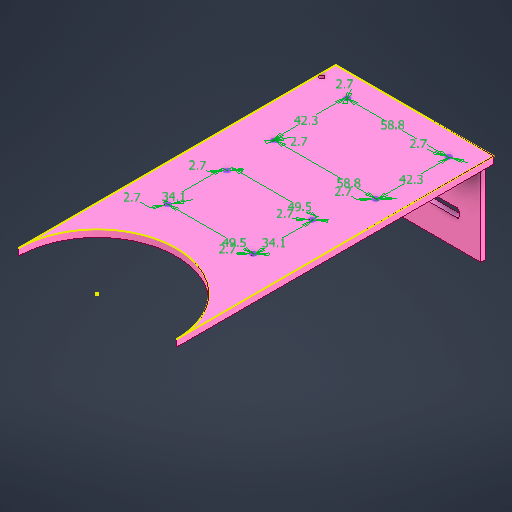
# Autodesk Inventor part: modificacao_tampa_base
Saved by Autodesk Inventor 2027.1 (Build 311270010, 270A)
## iProperties
Created: 2026-11-04
Part Number: modificacao_tampa_base
Material: Genérico
Document SubType Name: Modeling
Designer: Evellyn
Density: 1 g/cm^3
Appearance: Rosa
Author: Evellyn
Autodesk Inventor part; units mm, degrees
ref_plane "YZ Plane" through (0, 0, 0) normal (1, 0, 0) x (0, 1, 0)
ref_plane "XZ Plane" through (0, 0, 0) normal (0, 1, 0) x (-1, 0, 0)
ref_plane "XY Plane" through (0, 0, 0) normal (0, 0, 1) x (1, 0, 0)
sketch "Esboço1" plane through (0, 0, 0) normal (0, 1, 0) x (-1, 0, 0)
  line L0 (-45.75, -92) -> (45.75, -92)
  line L1 (45.75, -92) -> (45.75, 92)
  line L2 (-45.75, 92) -> (-45.75, -92)
  line L3 (-45.75, -92) -> (45.75, 92) construction
  line L4 (45.75, -92) -> (-45.75, 92) construction
  arc A0 (-45.75, 91.6728) -> (45.75, 91.6728) centre (0, 92) ccw
  arc A1 (45.75, 91.6728) -> (45.75, 92.3272) centre (0, 92) ccw
  arc A2 (-45.75, 92.3272) -> (-45.75, 91.6728) centre (0, 92) ccw
  point P0 (0, 0)
  dimension "d3" = 184
  dimension "d4" = 91.5
  constraints: 10 end point, 6 point on circle, 4 point on line, 3 centre point, 2 midpoint, 1 coincident, 1 horizontal, 1 parallel, 1 perpendicular
  measures "d3" distance of L0.end L1.end
  measures "d4" distance of L0.start L0.end
extrude "Extrusão1" add sketch "Esboço1" along normal blind 4
sketch "Esboço2" plane through (0, 0, 0) normal (0, -1, 0) x (1, 0, 0)
  line L0 (45.75, 91.6728) -> (45.75, -92) projected
  arc A0 (-45.75, 91.6728) -> (45.75, 91.6728) centre (0, 92) ccw projected
  line L1 (45.75, -92) -> (-45.75, -92) projected
  line L2 (-45.75, -92) -> (-45.75, 91.6728) projected
  line L3 (-41.75, -92) -> (41.25, -92)
  line L4 (41.25, -92) -> (41.25, -89)
  line L5 (41.25, -89) -> (-41.75, -89)
  line L6 (-41.75, -89) -> (-41.75, -92)
  line L7 (-41.75, -92) -> (41.25, -89) construction
  line L8 (41.25, -92) -> (-41.75, -89) construction
  point P0 (0, 0)
  point P1 (-0.25, -90.5)
  dimension "d7" = 3
  dimension "d8" = 4.5
  dimension "d9" = 83
  dimension "d10" = 0
  constraints: 12 end point, 2 midpoint, 2 parallel, 1 horizontal, 1 perpendicular
  measures "d7" distance of L3.end L4.end
  measures "d8" distance between parallel lines of L0 L4
  measures "d9" distance of L3.start L3.end
  measures "d10" distance between parallel lines of L1 L3
extrude "Extrusão2" add sketch "Esboço2" along normal blind 50 contours L1 L6 L5 L4
sketch "Esboço3" plane through (45.75, 4, -92) normal (0, 0, -1) x (-1, 0, 0)
  circle A0 centre (71.347, -29.4515) radius 5
  line L0 (18.0503, -33.5673) -> (36.0503, -33.5673)
  line L1 (37.0503, -34.5673) -> (37.0503, -37.5673)
  line L2 (36.0503, -38.5673) -> (18.0503, -38.5673)
  line L3 (17.0503, -37.5673) -> (17.0503, -34.5673)
  arc A1 (18.0503, -33.5673) -> (17.0503, -34.5673) centre (18.0503, -34.5673) ccw
  arc A2 (17.0503, -37.5673) -> (18.0503, -38.5673) centre (18.0503, -37.5673) ccw
  arc A3 (37.0503, -34.5673) -> (36.0503, -33.5673) centre (36.0503, -34.5673) ccw
  arc A4 (36.0503, -38.5673) -> (37.0503, -37.5673) centre (36.0503, -37.5673) ccw
  point P0 (45.75, -4)
  point P1 (37.0503, -38.5673)
  point P2 (37.0503, -33.5673)
  point P3 (17.0503, -38.5673)
  dimension "d13" = 10
  dimension "d14" = 20
  dimension "d15" = 5
  dimension "d16" = 1
  constraints: 8 end point, 8 point on circle, 8 tangent, 6 point on line, 5 centre point, 3 equal radius, 2 parallel, 1 horizontal, 1 perpendicular
  measures "d13" diameter of A0
  measures "d14" distance of point (37.05, -38.567) point (17.05, -38.567)
  measures "d15" distance of point (37.05, -33.567) point (37.05, -38.567)
  measures "d16" radius of A1
extrude "Extrusão3" cut sketch "Esboço3" against normal blind 50
sketch "Esboço4" plane through (0, 4, 0) normal (0, 1, 0) x (1, 0, 0)
  line L0 (-45.75, 92) -> (-45.75, -91.6728) projected
  arc A0 (45.75, -91.6728) -> (-45.75, -91.6728) centre (0, -92) ccw projected
  line L1 (45.75, -91.6728) -> (45.75, 92) projected
  line L2 (45.75, 92) -> (-45.75, 92) projected
  circle A1 centre (-24.3813, -26.7024) radius 1.35
  circle A2 centre (25.1187, -26.7024) radius 1.35
  circle A3 centre (-24.3813, 7.3976) radius 1.35
  circle A4 centre (25.1187, 7.3976) radius 1.35
  circle A5 centre (33.0687, 36.2863) radius 1.35
  circle A6 centre (33.0687, 78.5863) radius 1.35
  circle A7 centre (-25.7313, 36.2863) radius 1.35
  circle A8 centre (-25.7313, 78.5863) radius 1.35
  dimension "d28" = 2.7
  dimension "d31" = 2.7
  dimension "d32" = 49.5
  dimension "d33" = 2.7
  dimension "d35" = 34.1
  dimension "d36" = 2.7
  dimension "d37" = 49.5
  dimension "d38" = 34.1
  dimension "d49" = 2.7
  dimension "d52" = 2.7
  dimension "d53" = 42.3
  dimension "d62" = 2.7
  dimension "d63" = 58.8
  dimension "d64" = 2.7
  dimension "d65" = 42.3
  dimension "d66" = 58.8
  constraints: 8 centre point
  measures "d28" diameter of A1
  measures "d31" diameter of A2
  measures "d32" distance of A2.centre A1.centre
  measures "d33" diameter of A3
  measures "d35" distance of A1.centre A3.centre
  measures "d36" diameter of A4
  measures "d37" distance of A4.centre A3.centre
  measures "d38" distance of A2.centre A4.centre
  measures "d49" diameter of A5
  measures "d52" diameter of A6
  measures "d53" distance of A5.centre A6.centre
  measures "d62" diameter of A7
  measures "d63" distance of A5.centre A7.centre
  measures "d64" diameter of A8
  measures "d65" distance of A7.centre A8.centre
  measures "d66" distance of A6.centre A8.centre
hole "Furo1" at (-24.3813, 4, 26.7024) at (25.1187, 4, 26.7024) at (25.1187, 4, -7.3976) at (-24.3813, 4, -7.3976) direction (0, -1, 0) diameter 2.7 end through all
hole "Furo2" at (33.0687, 4, -36.2863) at (33.0687, 4, -78.5863) direction (0, -1, 0) diameter 2.7 end through all
hole "Furo3" at (-25.7313, 4, -78.5863) at (-25.7313, 4, -36.2863) direction (0, -1, 0) diameter 2.7 end through all
sketch "Esboço6" plane through (0, 4, 0) normal (0, 1, 0) x (1, 0, 0)
  line L0 (-41.75, 92) -> (-45.75, 92) projected
  line L1 (-45.75, 92) -> (-41.75, 92)
  line L2 (-41.75, 92) -> (-41.75, 72)
  line L3 (-41.75, 72) -> (-45.75, 72)
  line L4 (-45.75, 72) -> (-45.75, 92)
  circle A0 centre (-43.75, 82) radius 1.35
  point P0 (0, 0)
  dimension "d84" = 4
  dimension "d85" = 20
  dimension "d86" = 2.7
  constraints: 8 end point, 2 parallel, 1 centre point, 1 horizontal, 1 perpendicular
  measures "d84" distance of L2.end L3.end
  measures "d85" distance of L1.end L2.end
  measures "d86" diameter of A0
hole "Furo5" at (-43.75, 4, -82) direction (0, -1, 0) diameter 2.7 end through all
